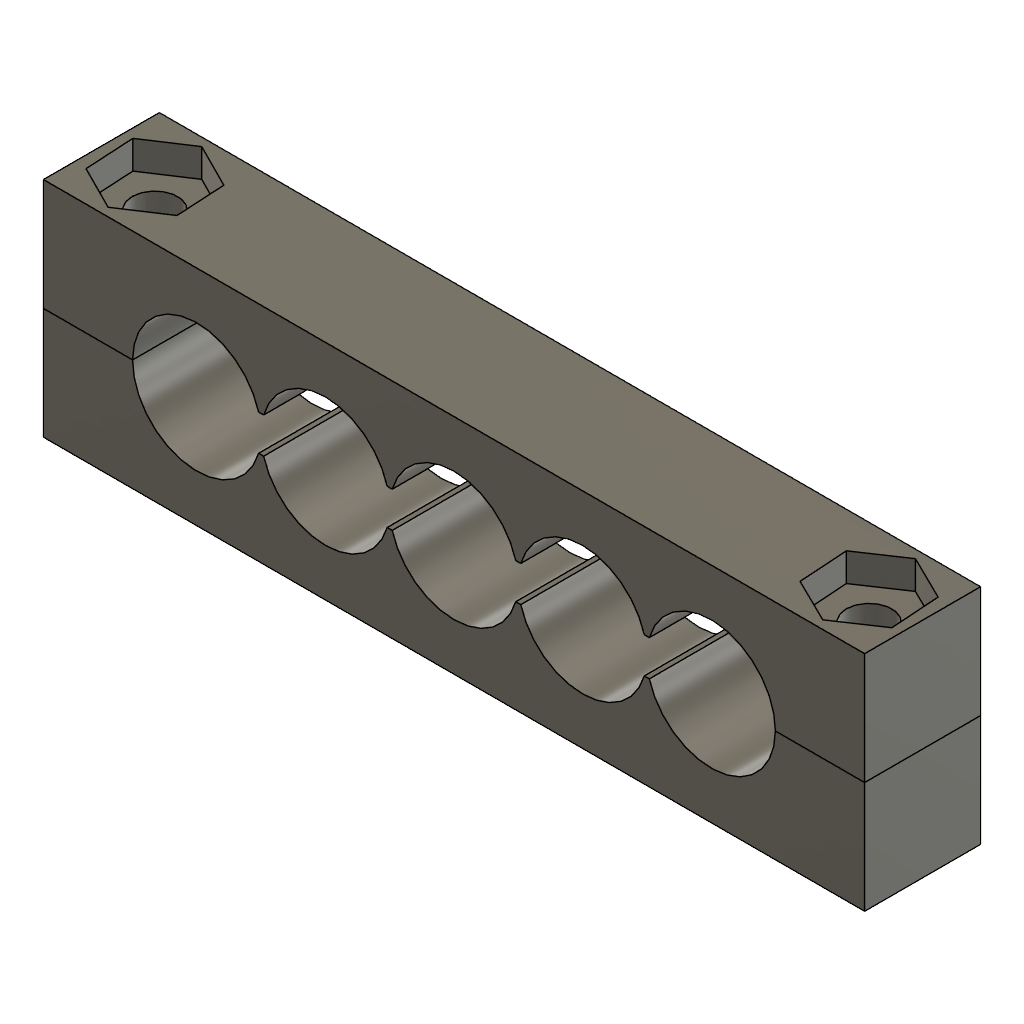
1Third_AA_Parametric (Autodesk Fusion 360 design; units mm, degrees)
Autodesk Fusion 360 part; units mm, degrees
sketch "Sketch1" plane through (0, 0, 0) normal (0, 0, 1) x (1, 0, 0)
  line L0 (0, 0) -> (92, 0)
  line L1 (92, 0) -> (92, 25)
  line L2 (92, 25) -> (0, 25)
  line L3 (0, 25) -> (0, 0)
  dimension "d1" = 92
  dimension "d2" = 25
  constraint horizontal L0
  constraint vertical L1
  constraint horizontal L2
  constraint vertical L3
  constraint coincident L0.start L3.end
  measures "d1" distance of L0.start L0.end
  measures "d2" distance of L0.start L2.end
extrude "Extrude1" add sketch "Sketch1" along normal blind 13 makes body 1
sketch "Sketch2" plane through (0, 0, 13) normal (0, 0, 1) x (1, 0, 0)
  line L0 (0, 25) -> (0, 0)
  line L1 (0, 0) -> (92, 0)
  line L2 (92, 0) -> (92, 25)
  line L3 (92, 25) -> (0, 25)
  line L4 (92, 12.5) -> (0, 12.5) construction
  circle A0 centre (17.2, 12.5) radius 7.2
  dimension "d9" = 14.4
  dimension "d20" = 17.2
  constraint midpoint L2 L4.start
  constraint midpoint L0 L4.end
  constraint coincident L4 A0.centre
  measures "d9" diameter of A0
  measures "d20" distance of L4.end A0.centre
extrude "Extrude2" cut sketch "Sketch2" against normal through all contours A0 bodies 1
pattern_linear "R-Pattern1" count 5 spacing 14.4 along (1, 0, 0) of "Extrude2"
sketch "Sketch3" plane through (0, 0, 13) normal (0, 0, 1) x (1, 0, 0)
  circle A0 centre (17.2, 12.5) radius 7.2
  line L0 (0, 25) -> (0, 0)
  line L1 (0, 0) -> (92, 0)
  line L2 (92, 0) -> (92, 25)
  line L3 (92, 25) -> (0, 25)
  line L4 (17.2436, 14.4995) -> (74.8, 14.5)
  line L5 (17.2396, 10.5004) -> (74.7611, 10.5004)
  arc A1 (17.2436, 14.4995) -> (17.2396, 10.5004) centre (17.2, 12.5) ccw
  arc A2 (74.7611, 10.5004) -> (74.8, 14.5) centre (74.8, 12.5) ccw
  arc A3 (53.2, 12.5) -> (38.8, 12.5) centre (46, 12.5) ccw
  arc A4 (67.6, 12.5) -> (53.2, 12.5) centre (60.4, 12.5) ccw
  arc A5 (38.8, 12.5) -> (24.4, 12.5) centre (31.6, 12.5) ccw
  circle A6 centre (74.8, 12.5) radius 7.2
  arc A7 (53.2, 12.5) -> (67.6, 12.5) centre (60.4, 12.5) ccw
  arc A8 (38.8, 12.5) -> (53.2, 12.5) centre (46, 12.5) ccw
  arc A9 (24.4, 12.5) -> (38.8, 12.5) centre (31.6, 12.5) ccw
  dimension "d16" = 4
  dimension "d17" = 4
  dimension "d41" = 12.5
  dimension "d42" = 57.6
  constraint concentric A0 A1
  constraint tangent L4 A2
  measures "d16" diameter of A1
  measures "d17" diameter of A2
  measures "d41" distance of L3 A2.centre
  measures "d42" distance of A0.centre A2.centre
extrude "Extrude3" cut sketch "Sketch3" against normal through all contours A0 L4 L5 A1 | A0 L5 A9 | A0 L4 A5 | L4 L5 A5 A9 | L4 A3 A5 | L5 A8 A9 | L4 L5 A3 A8 | L4 A3 A4 | L5 A7 A8 | L4 L5 A4 A7 | L4 A4 A6 | L5 A6 A7 | L4 L5 A2 A6 picked at (19.6277, 12.5) picked at (72.387, 12.5001) bodies 1
sketch "Sketch4" plane through (0, 0, 0) normal (0, -1, 0) x (1, 0, 0)
  line L0 (0, 0) -> (92, 0)
  line L1 (92, 0) -> (92, 13)
  line L2 (92, 13) -> (0, 13)
  line L3 (0, 13) -> (0, 0)
  line L4 (0, 6.5) -> (92, 6.5) construction
  point P0 (6, 6.5)
  point P1 (86, 6.5)
  dimension "d24" = 6
  dimension "d25" = 6
  constraint midpoint L3 L4.start
  constraint midpoint L1 L4.end
  constraint coincident L4 P0
  constraint coincident L4 P1
  measures "d24" distance of L3 P0
  measures "d25" distance of L1 P1
hole "Hole1" at (6, 0, 6.5) at (86, 0, 6.5) direction (0, 1, 0) diameter 5.105 depth 25 tip angle 180 counterbore diameter 9.525 counterbore depth 4.826 bodies 1
sketch "Sketch5" plane through (0, 25, 0) normal (0, 1, 0) x (-1, 0, 0)
  circle A0 centre (-6, 6.5) radius 2.5525
  circle A1 centre (-86, 6.5) radius 2.5525
  line L0 (-92, 0) -> (0, 0)
  line L1 (0, 0) -> (0, 13)
  line L2 (0, 13) -> (-92, 13)
  line L3 (-92, 13) -> (-92, 0)
  line L4 (-1.0229, 3.9935) -> (-1.3408, 9.5571)
  line L5 (-1.3408, 9.5571) -> (-6.3179, 12.0635)
  line L6 (-6.3179, 12.0635) -> (-10.9771, 9.0065)
  line L7 (-10.9771, 9.0065) -> (-10.6592, 3.4429)
  line L8 (-10.6592, 3.4429) -> (-5.6821, 0.9365)
  line L9 (-5.6821, 0.9365) -> (-1.0229, 3.9935)
  line L10 (-90.6281, 3.3961) -> (-85.626, 0.94)
  line L11 (-85.626, 0.94) -> (-80.9979, 4.0439)
  line L12 (-80.9979, 4.0439) -> (-81.3719, 9.6039)
  line L13 (-81.3719, 9.6039) -> (-86.374, 12.06)
  line L14 (-86.374, 12.06) -> (-91.0021, 8.9561)
  line L15 (-91.0021, 8.9561) -> (-90.6281, 3.3961)
  point P0 (-6, 6.5)
  point P1 (-86, 6.5)
  dimension "d32" = 4.826
  dimension "d33" = 4.826
  constraint coincident P0 A0.centre
  constraint coincident P1 A1.centre
  measures "d32" distance of P0 L9
  measures "d33" distance of P1 L15
extrude "Extrude4" cut sketch "Sketch5" against normal blind 3.175 contours L4 L5 L6 L7 L8 L9 | L10 L11 L12 L13 L14 L15 bodies 1
sketch "Sketch6" plane through (0, 0, 0) normal (0, 0, -1) x (-1, 0, 0)
  line L0 (0, 0) -> (0, 25)
  line L1 (0, 25) -> (-92, 25)
  line L2 (-92, 25) -> (-92, 0)
  line L3 (-92, 0) -> (0, 0)
  line L4 (-39.0833, 14.4997) -> (-38.5167, 14.4997)
  arc A0 (-24.1168, 10.5004) -> (-24.1168, 14.4996) centre (-17.2, 12.5) ccw
  line L5 (-24.1168, 10.5004) -> (-24.6832, 10.5004)
  line L6 (-92, 12.5) -> (0, 12.5)
  arc A1 (-24.6832, 14.4996) -> (-38.5167, 14.4997) centre (-31.6, 12.5) ccw
  line L7 (-24.6832, 14.4996) -> (-24.1168, 14.4996)
  arc A2 (-38.5168, 10.5004) -> (-24.6832, 10.5004) centre (-31.6, 12.5) ccw
  line L8 (-38.5168, 10.5004) -> (-39.0832, 10.5004)
  arc A3 (-52.9168, 10.5004) -> (-39.0832, 10.5004) centre (-46, 12.5) ccw
  line L9 (-52.9168, 10.5004) -> (-53.4832, 10.5004)
  arc A4 (-67.3168, 10.5004) -> (-53.4832, 10.5004) centre (-60.4, 12.5) ccw
  line L10 (-53.4833, 14.4998) -> (-52.9167, 14.4998)
  arc A5 (-39.0833, 14.4997) -> (-52.9167, 14.4998) centre (-46, 12.5) ccw
  line L11 (-67.3168, 10.5004) -> (-67.8832, 10.5004)
  arc A6 (-67.8833, 14.4999) -> (-67.8832, 10.5004) centre (-74.8, 12.5) ccw
  line L12 (-67.8833, 14.4999) -> (-67.3167, 14.4999)
  arc A7 (-53.4833, 14.4998) -> (-67.3167, 14.4999) centre (-60.4, 12.5) ccw
  constraint midpoint L2 L6.start
  constraint midpoint L0 L6.end
split "Split1" by curves path "Sketch6" along L6 bodies 1 makes body 2 at (33.1346, 0, 12.3503)
equation "d1 = Length"
equation "d2 = Width"
equation "d3 = Height"
equation "d9 = CellDia"
equation "Width = 25 mm"
equation "Length = Num_Cells * CellDia + 20 mm"
equation "Height = 13 mm"
equation "CellDia = 14.4 mm"
equation "d16 = SegmentWidth"
equation "d17 = d16"
equation "SegmentWidth = 4 mm"
equation "d20 = ( Length - ( Num_Cells - 1 ) * CellDia ) / 2"
equation "d24 = ScrewSpace"
equation "d25 = d24"
equation "d26 = Width"
equation "ScrewSpace = 6 mm"
equation "Num_Cells = 5"
equation "d37 = Num_Cells"
equation "d39 = CellDia"
equation "d41 = Width / 2"
equation "d42 = ( Num_Cells - 1 ) * CellDia"
